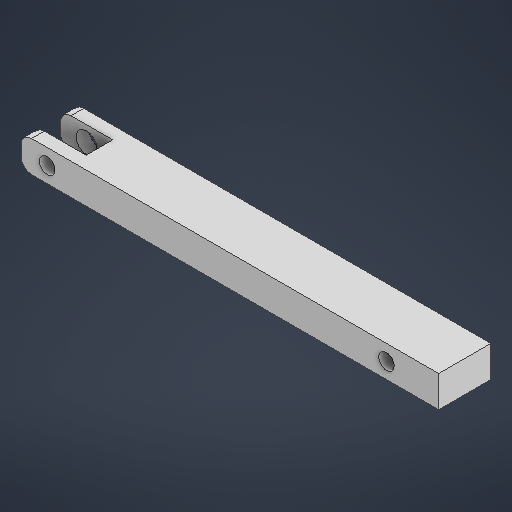
# Autodesk Inventor part: BottomLeg
Saved by Autodesk Inventor 2027.2 (Build 312334000, 334)
## iProperties
Created: 2026-11-21
Part Number: BottomLeg
Material: Generic
Document SubType Name: Modeling
Designer: junha
Density: 1 g/cm^3
Appearance: Default
Author: junha
Autodesk Inventor part; units mm, degrees
ref_plane "YZ Plane" through (0, 0, 0) normal (1, 0, 0) x (0, 1, 0)
ref_plane "XZ Plane" through (0, 0, 0) normal (0, 1, 0) x (-1, 0, 0)
ref_plane "XY Plane" through (0, 0, 0) normal (0, 0, 1) x (1, 0, 0)
sketch "Sketch1" plane through (0, 0, 0) normal (0, 0, 1) x (1, 0, 0)
  line L0 (0, 0) -> (80, 0)
  line L1 (80, 0) -> (80, 6)
  line L2 (80, 6) -> (0, 6)
  line L3 (0, 6) -> (0, 0)
  dimension "d0" = 80
  dimension "d1" = 6
  constraints: 8 end point, 3 perpendicular, 1 horizontal
  measures "d0" distance of L0.start L0.end
  measures "d1" distance of L0.end L1.end
extrude "Extrusion1" add sketch "Sketch1" along normal blind 10
sketch "Sketch2" plane through (0, 0, 0) normal (-1, 0, 0) x (0, 0, 1)
  line L0 (0, 0) -> (0, 6) projected
  line L1 (0, 6) -> (2.45, 6)
  line L2 (0, 6) -> (10, 6) projected
  line L3 (2.45, 6) -> (2.45, 0)
  line L4 (0, 0) -> (10, 0) projected
  line L5 (10, 0) -> (10, 6) projected
  line L6 (10, 6) -> (7.55, 6)
  line L7 (7.55, 6) -> (7.55, 0)
  line L8 (2.45, 6) -> (7.55, 6)
  line L9 (7.55, 6) -> (7.55, 0)
  line L10 (7.55, 0) -> (2.45, 0)
  line L11 (2.45, 0) -> (2.45, 6)
  point P0 (7.55, 0)
  dimension "d4" = 2.45
  dimension "d5" = 2.45
  constraints: 16 end point, 3 parallel, 3 point on line, 2 perpendicular, 1 horizontal
  measures "d4" distance of L0.end L1.end
  measures "d5" distance of L2.end L6.end
extrude "Extrusion2" cut sketch "Sketch2" against normal blind 10 contours L3 L2 L7 L4
sketch "Sketch3" plane through (0, 0, 2.45) normal (0, 0, 1) x (1, 0, 0)
  line L0 (0, 6) -> (10, 6) projected
  line L1 (5, 6) -> (5, 0)
  line L2 (0, 0) -> (0, 6) projected
  line L3 (0, 3) -> (10, 3)
  line L4 (10, 0) -> (10, 6) projected
  circle A0 centre (5, 3) radius 2
  dimension "d8" = 4
  constraints: 4 end point, 4 midpoint, 1 centre point, 1 vertical
  measures "d8" diameter of A0
extrude "Extrusion3" cut sketch "Sketch3" against normal blind 4 contours A0 L3 L1 | L1 L3 A0 | L3 L1 A0 | L3 A0 L1
sketch "Sketch4" plane through (0, 0, 7.55) normal (0, 0, -1) x (-1, 0, 0)
  circle A0 centre (-5, 3) radius 2 projected
  circle A1 centre (-5, 3) radius 1.5
  point P0 (0, 0)
  dimension "d11" = 3
  constraints: 1 centre point, 1 coincident
  measures "d11" diameter of A1
extrude "Extrusion4" cut sketch "Sketch4" against normal blind 11.25 contours A1
sketch "Sketch5" plane through (0, 0, 10) normal (0, 0, 1) x (1, 0, 0)
  line L0 (80, 0) -> (80, 6) projected
  line L1 (80, 3) -> (70, 3)
  circle A0 centre (70, 3) radius 1.5
  point P0 (0, 0)
  dimension "d14" = 10
  dimension "d15" = 3
  constraints: 2 end point, 1 centre point, 1 coincident, 1 horizontal, 1 midpoint
  measures "d14" distance of L1.start L1.end
  measures "d15" diameter of A0
extrude "Extrusion5" cut sketch "Sketch5" against normal blind 10
fillet "Fillet1" radius 2 4 edges at (0, 6, 1.225) (0, 0, 1.225) (0, 6, 8.775) (0, 0, 8.775)
equation "\"d9\" = d8"
body "Solid1"
